4inPathfinder (Autodesk Fusion 360 design; units mm, degrees)
Autodesk Fusion 360 part; units mm, degrees
sketch "Sketch1" plane through (0, 0, 0) normal (0, 1, 0) x (1, 0, 0)
sketch "Sketch2" plane through (0, 0, 0) normal (0, 1, 0) x (1, 0, 0)
  circle A0 centre (59.500001, -11.5) radius 1
  line L0 (59.500001, -11.5) -> (39.500001, -11.5)
  circle A1 centre (39.500001, -11.5) radius 1
  line L1 (39.500001, -11.5) -> (39.500001, -31.5)
  circle A2 centre (39.500001, -31.5) radius 1
  line L2 (39.500001, -31.5) -> (59.500001, -31.5)
  circle A3 centre (59.500001, -31.5) radius 1
  line L3 (59.500001, -31.5) -> (59.500001, -11.5)
  line L4 (59.500001, -21.5) -> (49.500001, -21.5)
  line L5 (49.500001, -21.5) -> (49.500001, -40)
  line L6 (49.500001, -21.5) -> (68.000001, -21.5)
  line L7 (68.000001, -21.5) -> (49.500001, -40)
  line L8 (49.500001, -21.5) -> (49.500001, -3)
  line L9 (49.500001, -21.5) -> (31.000001, -21.5)
  line L10 (68.000001, -21.5) -> (49.500001, -3)
  line L11 (49.500001, -3) -> (31.000001, -21.5)
  line L12 (31.000001, -21.5) -> (49.500001, -40)
  circle A4 centre (49.500001, -3) radius 1.75
  circle A5 centre (31.000001, -21.5) radius 1.75
  circle A6 centre (49.500001, -40) radius 1.75
  circle A7 centre (68.000001, -21.5) radius 1.75
  line L13 (49.500001, -21.5) -> (70.500001, -21.5)
  line L14 (49.500001, -21.5) -> (49.500001, -42.5)
  line L15 (49.500001, -21.5) -> (48.000001, -21.5)
  line L16 (49.500001, -21.5) -> (28.500001, -21.5)
  line L17 (49.500001, -21.5) -> (49.500001, -0.5)
  line L18 (70.500001, -21.5) -> (49.500001, -0.5)
  line L19 (49.500001, -0.5) -> (28.500001, -21.5)
  line L20 (28.500001, -21.5) -> (49.500001, -42.5)
  line L21 (49.500001, -42.5) -> (70.500001, -21.5)
  line L22 (49.500001, -21.5) -> (49.500001, -44.500001)
  line L23 (49.500001, -21.5) -> (26.500001, -21.5)
  line L24 (49.500001, -21.5) -> (49.500001, 1.5)
  line L25 (49.500001, -21.5) -> (72.500001, -21.5)
  line L26 (72.500001, -21.5) -> (49.500001, 1.5)
  line L27 (49.500001, 1.5) -> (26.500001, -21.5)
  line L28 (26.500001, -21.5) -> (49.500001, -44.500001)
  line L29 (49.500001, -44.500001) -> (72.500001, -21.5)
  circle A8 centre (59.500001, -31.5) radius 1.875
  circle A9 centre (59.500001, -11.5) radius 1.875
  circle A10 centre (39.500001, -11.5) radius 1.875
  circle A11 centre (39.500001, -31.5) radius 1.875
  dimension "d1" = 2
  dimension "d2" = 20
  dimension "d3" = 2
  dimension "d4" = 20
  dimension "d5" = 2
  dimension "d6" = 20
  dimension "d7" = 2
  dimension "d8" = 18.5
  dimension "d9" = 18.5
  dimension "d10" = 18.5
  dimension "d11" = 18.5
  dimension "d12" = 3.5
  dimension "d13" = 3.5
  dimension "d14" = 3.5
  dimension "d15" = 3.5
  dimension "d16" = 21
  dimension "d17" = 21
  dimension "d18" = 21
  dimension "d19" = 21
  dimension "d20" = 23
  dimension "d21" = 23
  dimension "d22" = 23
  dimension "d52" = 3.75
  dimension "d53" = 3.75
  dimension "d54" = 3.75
  dimension "d55" = 3.75
  constraint horizontal L0
  constraint perpendicular L0 L1
  constraint perpendicular L1 L2
  constraint perpendicular L3 L4
  constraint perpendicular L4 L5
  constraint perpendicular L5 L6
  constraint perpendicular L0 L8
  constraint perpendicular L8 L9
  constraint perpendicular L5 L13
  constraint perpendicular L13 L14
  constraint perpendicular L8 L15
  constraint perpendicular L8 L16
  constraint perpendicular L4 L17
  constraint perpendicular L4 L22
  constraint perpendicular L5 L23
  constraint perpendicular L9 L24
  constraint perpendicular L5 L25
  constraint concentric A3 A8
  constraint concentric A0 A9
  constraint concentric A1 A10
  measures "d1" diameter of A0
  measures "d3" diameter of A1
  measures "d5" diameter of A2
  measures "d7" diameter of A3
  measures "d12" diameter of A4
  measures "d13" diameter of A5
  measures "d14" diameter of A6
  measures "d15" diameter of A7
  measures "d52" diameter of A8
  measures "d53" diameter of A9
  measures "d54" diameter of A10
  measures "d55" diameter of A11
extrude "Extrude1" add sketch "Sketch2" along normal blind 1 contours A0 L3 L10 L18 A9 | A0 L0 L10 L18 A9 | A0 L0 L3 L10 | L10 A7 L13 L18 L25 A9 | L10 A4 L17 L18 L24 A9 | L3 L10 A9 | L0 L3 L10 A9 | L7 A7 L13 L21 L25 A8 | L3 L6 L10 A7 L13 L25 A9 | L0 L10 A9 | L11 A4 L17 L19 L24 A10 | L0 L8 L10 A4 L17 L24 A9 | L0 L3 L4 L6 L8 L13 L17 L24 L25 A9 | A3 L3 L7 L21 A8 | L0 A1 L11 L19 A10 | L3 L6 L7 A7 L13 L25 A8 | L2 L3 L4 L5 L6 L13 L14 L22 L25 A8 | L3 L7 A8 | L0 L1 L8 L9 L15 L16 L17 L23 L24 A10 | L0 L8 L11 A4 L17 L24 A10 | L0 L11 A10 | L11 A5 L16 L19 L23 A10 | A1 L1 L11 L19 A10 | L2 L3 L7 A8 | L1 L2 L5 L9 L14 L15 L16 L22 L23 A11 | L2 A3 L3 L7 | L2 A3 L7 L21 A8 | L7 A6 L14 L21 L22 A8 | L12 A6 L14 L20 L22 A11 | L0 L1 L11 A10 | L0 A1 L1 L11 | L12 A5 L16 L20 L23 A11 | L1 L9 L11 A5 L16 L23 A10 | L1 L11 A10 | L2 L5 L7 A6 L14 L22 A8 | L2 L7 A8 | L2 L5 L12 A6 L14 L22 A11 | A2 L2 L12 L20 A11 | L1 A2 L12 L20 A11 | L2 L12 A11 | L1 L2 L12 A11 | L1 L9 L12 A5 L16 L23 A11 | L1 L12 A11 | L1 A2 L2 L12 picked at (59.79364, -12.912059) picked at (58.087942, -11.206361) picked at (58.336727, -11.547438) picked at (62.703057, -15.391881) picked at (55.60812, -8.296944) picked at (59.538338, -13.248823) picked at (58.527657, -12.409288) picked at (62.703057, -27.608119) picked at (61.984979, -18.42599) picked at (57.751178, -11.461663) picked at (43.391882, -8.296944) picked at (52.574011, -9.015022) picked at (55.75738, -18.63901) picked at (59.79364, -30.087941) picked at (40.91206, -11.206361) picked at (61.984979, -24.57401) picked at (55.75738, -24.36099) picked at (59.538338, -29.751177) picked at (46.192451, -15.171234) picked at (46.425991, -9.015022) picked at (41.248824, -11.461663) picked at (36.296945, -15.391881) picked at (39.206362, -12.912059) picked at (58.527657, -30.590712) picked at (46.192451, -27.828766) picked at (59.452563, -30.336726) picked at (58.087942, -31.793639) picked at (55.60812, -34.703056) picked at (43.391882, -34.703056) picked at (40.472344, -12.409288) picked at (39.547439, -12.663274) picked at (36.296945, -27.608119) picked at (37.015023, -18.42599) picked at (39.461664, -13.248823) picked at (52.574011, -33.984979) picked at (57.751178, -31.538337) picked at (46.425991, -33.984979) picked at (40.91206, -31.793639) picked at (39.206362, -30.087941) picked at (41.248824, -31.538337) picked at (40.472344, -30.590712) picked at (37.015023, -24.57401) picked at (39.461664, -29.751177) picked at (39.547439, -30.336726) makes body 1
extrude "Extrude2" add sketch "Sketch2" along normal blind 2 contours A0 L18 A9 | L18 L24 L25 L26 A9 | L21 L22 L25 L29 A8 | L19 L23 L24 L27 A10 | A3 L21 A8 | A1 L19 A10 | L20 L22 L23 L28 A11 | A2 L20 A11 picked at (59.441403, -9.921136) picked at (52.847913, -2.87517) picked at (52.847913, -40.12483) picked at (30.875643, -18.138345) picked at (59.441403, -33.078865) picked at (38.467837, -10.303858) picked at (46.138345, -40.124358) picked at (38.467837, -32.696143) bodies 1
extrude "Extrude3" cut 1 faces at (46.119229, 2, 39.829941) along direction (0, -1, 0) blind 1 on bodies 1 bodies 1
extrude "Extrude4" add 1 faces at (57.166668, 0.333333, 36.833334) along direction (0.70710679, 0, 0.70710677) blind 1 on bodies 1 bodies 1
extrude "Extrude5" add 1 faces at (34.166668, 0.333333, 29.166667) along direction (-0.70710679, 0, 0.70710677) blind 1 on bodies 1 bodies 1
extrude "Extrude6" add 1 faces at (49.735703, 0.333333, 44.735703) along direction (-0.70710677, 0, 0.70710679) blind 1 on bodies 1 bodies 1
extrude "Extrude7" add 1 faces at (26.264299, 0.333333, 21.735702) along direction (-0.70710677, 0, -0.70710679) blind 1 on bodies 1 bodies 1
extrude "Extrude8" add 1 faces at (41.833334, 0.333333, 6.166667) along direction (-0.70710678, 0, -0.70710678) blind 1 on bodies 1 bodies 1
extrude "Extrude9" add 1 faces at (56.695263, 0.333333, 5.695262) along direction (0.70710678, 0, -0.70710678) blind 1 on bodies 1 bodies 1
extrude "Extrude10" add 1 faces at (72.735703, 0.333333, 21.735702) along direction (0.70710677, 0, -0.70710679) blind 1 on bodies 1 bodies 1
sketch "Sketch3" plane through (0, 1, 0) normal (0, 1, 0) x (-1, 0, 0)
  circle A0 centre (-39.500001, 11.5) radius 1
  circle A1 centre (-39.500001, 31.5) radius 1
  circle A2 centre (-59.500001, 11.5) radius 1
  line L0 (-49.500001, -2.914213) -> (-25.792894, 20.792893)
  line L1 (-25.792894, 20.792893) -> (-25.085787, 21.5)
  line L2 (-25.085787, 21.5) -> (-48.792894, 45.207107)
  line L3 (-48.792894, 45.207107) -> (-49.500001, 45.914214)
  line L4 (-49.500001, 45.914214) -> (-73.914214, 21.5)
  line L5 (-73.914214, 21.5) -> (-73.207108, 20.792893)
  line L6 (-73.207108, 20.792893) -> (-49.500001, -2.914213)
  circle A3 centre (-68.000001, 21.5) radius 1.75
  circle A4 centre (-49.500001, 3) radius 1.75
  circle A5 centre (-31.000001, 21.5) radius 1.75
  circle A6 centre (-49.500001, 40) radius 1.75
  circle A7 centre (-59.500001, 31.5) radius 1
  line L7 (-25.085787, 21.5) -> (-24.378681, 20.792893)
  line L8 (-49.500001, -2.914213) -> (-48.792894, -3.62132)
  line L9 (-49.500001, -2.914213) -> (-50.207108, -3.62132)
  line L10 (-73.914214, 21.5) -> (-74.621321, 20.792893)
  line L11 (-73.914214, 21.5) -> (-74.621321, 22.207107)
  line L12 (-49.500001, 45.914214) -> (-50.207108, 46.621321)
  line L13 (-49.500001, 45.914214) -> (-48.792894, 46.621321)
  line L14 (-25.085787, 21.5) -> (-24.378681, 22.207107)
  line L15 (-24.378681, 22.207107) -> (-48.792894, 46.621321)
  line L16 (-50.207108, 46.621321) -> (-74.621321, 22.207107)
  line L17 (-74.621321, 20.792893) -> (-50.207108, -3.62132)
  line L18 (-48.792894, -3.62132) -> (-24.378681, 20.792893)
  line L19 (-24.378681, 22.207107) -> (-24.378681, 20.792893)
  line L20 (-74.621321, 20.792893) -> (-74.621321, 22.207107)
  line L21 (-48.792894, 46.621321) -> (-50.207108, 46.621321)
  line L22 (-48.792894, -3.62132) -> (-50.207108, -3.62132)
  line L23 (-48.792894, -3.62132) -> (-24.378681, 20.792893)
  line L24 (-24.378681, 20.792893) -> (-24.378681, 22.207107)
  dimension "d43" = 1
  dimension "d44" = 1
  dimension "d45" = 1
  dimension "d46" = 1
  dimension "d47" = 1
  dimension "d48" = 1
  dimension "d49" = 1
  constraint perpendicular L1 L7
  constraint perpendicular L0 L8
  constraint perpendicular L8 L9
  constraint perpendicular L5 L10
  constraint perpendicular L4 L11
  constraint perpendicular L4 L12
  constraint perpendicular L3 L13
  constraint perpendicular L7 L14
extrude "Extrude11" add sketch "Sketch3" against normal blind 1 contours L5 L6 L9 L10 L17 | L0 L1 L7 L8 L18 L23 | L8 L9 L22 | L7 L14 L19 L24 | L2 L3 L13 L14 L15 | L4 L11 L12 L16 | L10 L11 L20 | L12 L13 L21 picked at (-66.011846, 12.654822) picked at (-32.988156, 12.654822) picked at (-49.500001, -3.385618) picked at (-24.614383, 21.5) picked at (-40.654823, 38.011845) picked at (-66.247548, 30.109476) picked at (-74.385619, 21.5) picked at (-49.500001, 46.385619) bodies 1
extrude "Extrude12" add sketch "Sketch2" against normal blind 0.8 separate body contours L18 L24 L25 L26 A9 | L10 A7 L13 L18 L25 A9 | L10 A4 L17 L18 L24 A9 | L7 A7 L13 L21 L25 A8 | L21 L22 L25 L29 A8 | L3 L6 L10 A7 L13 L25 A9 | L11 A4 L17 L19 L24 A10 | L19 L23 L24 L27 A10 | L0 L8 L10 A4 L17 L24 A9 | L0 L3 L4 L6 L8 L13 L17 L24 L25 A9 | L3 L6 L7 A7 L13 L25 A8 | L2 L3 L4 L5 L6 L13 L14 L22 L25 A8 | L20 L22 L23 L28 A11 | L0 L1 L8 L9 L15 L16 L17 L23 L24 A10 | L0 L8 L11 A4 L17 L24 A10 | L11 A5 L16 L19 L23 A10 | L1 L2 L5 L9 L14 L15 L16 L22 L23 A11 | L7 A6 L14 L21 L22 A8 | L12 A6 L14 L20 L22 A11 | L12 A5 L16 L20 L23 A11 | L1 L9 L11 A5 L16 L23 A10 | L2 L5 L7 A6 L14 L22 A8 | L2 L5 L12 A6 L14 L22 A11 | L1 L9 L12 A5 L16 L23 A11 picked at (52.847913, -2.87517) picked at (62.703057, -15.391881) picked at (55.60812, -8.296944) picked at (62.703057, -27.608119) picked at (52.847913, -40.12483) picked at (61.984979, -18.42599) picked at (43.391882, -8.296944) picked at (30.875643, -18.138345) picked at (52.574011, -9.015022) picked at (55.75738, -18.63901) picked at (61.984979, -24.57401) picked at (55.75738, -24.36099) picked at (46.138345, -40.124358) picked at (46.192451, -15.171234) picked at (46.425991, -9.015022) picked at (36.296945, -15.391881) picked at (46.192451, -27.828766) picked at (55.60812, -34.703056) picked at (43.391882, -34.703056) picked at (36.296945, -27.608119) picked at (37.015023, -18.42599) picked at (52.574011, -33.984979) picked at (46.425991, -33.984979) picked at (37.015023, -24.57401) makes body 2
extrude "Extrude13" add sketch "Sketch3" against normal blind 12 contours L5 L6 L9 L10 L17 | L0 L1 L7 L8 L18 L23 | L8 L9 L22 | L7 L14 L19 L24 | L2 L3 L13 L14 L15 | L4 L11 L12 L16 | L10 L11 L20 | L12 L13 L21 picked at (-66.011846, 12.654822) picked at (-32.988156, 12.654822) picked at (-49.500001, -3.385618) picked at (-24.614383, 21.5) picked at (-40.654823, 38.011845) picked at (-66.247548, 30.109476) picked at (-74.385619, 21.5) picked at (-49.500001, 46.385619) bodies 1
extrude "Extrude14" add 1 faces at (46.639011, -0.8, 18.575955) along direction (0, -1, 0) blind 1 on bodies 2 bodies 2
sketch "Sketch4" plane through (0, -11, 0) normal (0, -1, 0) x (1, 0, 0)
  line L0 (73.207108, 20.792893) -> (49.500001, -2.914213)
  line L1 (49.500001, -2.914213) -> (25.792894, 20.792893)
  line L2 (25.792894, 20.792893) -> (25.085787, 21.5)
  line L3 (25.085787, 21.5) -> (48.792894, 45.207107)
  line L4 (48.792894, 45.207107) -> (49.500001, 45.914214)
  line L5 (49.500001, 45.914214) -> (73.914214, 21.5)
  line L6 (73.914214, 21.5) -> (73.207108, 20.792893)
  line L7 (24.378681, 20.792893) -> (48.792894, -3.62132)
  line L8 (48.792894, -3.62132) -> (50.207108, -3.62132)
  line L9 (50.207108, -3.62132) -> (74.621321, 20.792893)
  line L10 (74.621321, 20.792893) -> (74.621321, 22.207107)
  line L11 (74.621321, 22.207107) -> (50.207108, 46.621321)
  line L12 (50.207108, 46.621321) -> (48.792894, 46.621321)
  line L13 (48.792894, 46.621321) -> (24.378681, 22.207107)
  line L14 (24.378681, 22.207107) -> (24.378681, 20.792893)
  line L15 (49.500001, 20.792893) -> (37.646447, 8.93934)
  line L16 (49.500001, 20.792893) -> (61.353232, 8.939662)
  line L17 (49.500001, 20.792893) -> (61.353232, 32.646124)
  line L18 (49.500001, 20.792893) -> (37.64677, 32.646124)
  line L19 (37.646447, 8.93934) -> (39.414214, 7.171573)
  line L20 (39.414214, 7.171573) -> (38.707108, 6.464466)
  line L21 (38.707108, 6.464466) -> (35.171574, 10)
  line L22 (35.171574, 10) -> (35.878681, 10.707107)
  line L23 (37.646447, 8.93934) -> (35.878681, 10.707107)
  line L24 (37.64677, 32.646124) -> (35.879003, 30.878357)
  line L25 (35.879003, 30.878357) -> (35.171574, 31.585787)
  line L26 (35.171574, 31.585787) -> (38.707108, 35.121321)
  line L27 (38.707108, 35.121321) -> (39.414214, 34.414214)
  line L28 (39.414214, 34.414214) -> (37.64677, 32.646124)
  line L29 (38.707108, 35.121321) -> (38.000001, 35.828427)
  line L30 (35.171574, 31.585787) -> (34.464467, 32.292893)
  line L31 (61.353232, 32.646124) -> (59.585465, 34.413891)
  line L32 (59.585465, 34.413891) -> (61.000001, 35.828427)
  line L33 (61.000001, 35.828427) -> (64.535535, 32.292893)
  line L34 (64.535535, 32.292893) -> (63.121321, 30.87868)
  line L35 (63.121321, 30.87868) -> (61.353232, 32.646124)
  line L36 (61.353232, 8.939662) -> (63.120999, 10.707429)
  line L37 (63.120999, 10.707429) -> (63.828428, 10)
  line L38 (63.828428, 10) -> (60.292894, 6.464466)
  line L39 (60.292894, 6.464466) -> (59.585787, 7.171573)
  line L40 (61.353232, 8.939662) -> (59.585787, 7.171573)
  dimension "d62" = 16.763
  dimension "d63" = 16.763
  dimension "d64" = 16.763
  dimension "d65" = 2.5
  dimension "d66" = 5
  dimension "d67" = 2.5
  dimension "d68" = 5
  dimension "d69" = 1
  dimension "d70" = 2.5
  dimension "d71" = 5
  dimension "d72" = 2
  dimension "d73" = 2.5
  dimension "d74" = 5
  constraint perpendicular L1 L15
  constraint perpendicular L15 L16
  constraint perpendicular L16 L17
  constraint perpendicular L17 L18
  constraint perpendicular L15 L19
  constraint perpendicular L7 L20
  constraint perpendicular L20 L21
  constraint perpendicular L1 L22
  constraint perpendicular L1 L24
  constraint perpendicular L3 L25
  constraint perpendicular L25 L26
  constraint perpendicular L26 L27
  constraint perpendicular L13 L29
  constraint perpendicular L13 L30
  constraint perpendicular L17 L31
  constraint perpendicular L11 L32
  constraint perpendicular L32 L33
  constraint perpendicular L5 L34
  constraint perpendicular L16 L36
  constraint perpendicular L9 L37
  constraint perpendicular L37 L38
  constraint perpendicular L0 L39
extrude "Extrude15" add 1 faces at (57.166668, -0.6, 36.833334) along direction (0.70710679, 0, 0.70710677) blind 1 on bodies 2 bodies 2
extrude "Extrude16" add 1 faces at (41.833334, -1.2, 36.833334) along direction (-0.70710679, 0, 0.70710677) blind 1 on bodies 2 bodies 2
extrude "Extrude17" add 1 faces at (49.264299, -1.2, 44.735703) along direction (0.70710677, 0, 0.70710679) blind 1 on bodies 2 bodies 2
extrude "Extrude18" add 1 faces at (34.166668, -1.2, 13.833334) along direction (-0.70710678, 0, -0.70710678) blind 1 on bodies 2 bodies 2
extrude "Extrude19" add 1 faces at (26.264299, -1.2, 21.735702) along direction (-0.70710677, 0, -0.70710679) blind 1 on bodies 2 bodies 2
extrude "Extrude20" add 1 faces at (56.695263, -0.6, 5.695262) along direction (0.70710678, 0, -0.70710678) blind 1 on bodies 2 bodies 2
extrude "Extrude21" add 1 faces at (72.735703, -0.6, 21.735702) along direction (0.70710677, 0, -0.70710679) blind 1 on bodies 2 bodies 2
extrude "Extrude22" cut sketch "Sketch4" against normal blind 9.2 contours L0 L9 L36 L37 L38 L39 L40 | L5 L11 L32 L33 L34 | L1 L7 L19 L20 L21 L22 L23 | L3 L13 L26 L29 L30 picked at (61.824959, 8.467935) picked at (62.885619, 33) picked at (37.175043, 8.467935) picked at (36.114383, 33) bodies 1
sketch "Sketch5" plane through (0, 0, 0) normal (0, 1, 0) x (1, 0, 0)
